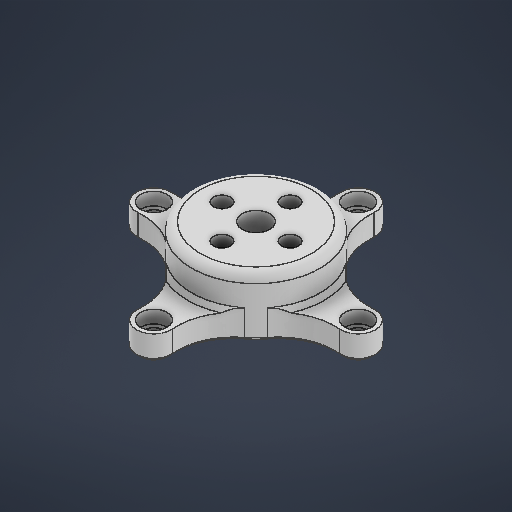
# Autodesk Inventor part: roter
Saved by Autodesk Inventor 2026.2 (Build 302298010, 298A)
## iProperties
Created: 2026-04-12
Part Number: roter
Material: 일반
Document SubType Name: Modeling
Designer: work
Density: 1 g/cm^3
Appearance: 기본값
Author: work
Autodesk Inventor part; units mm, degrees
ref_plane "YZ Plane" through (0, 0, 0) normal (1, 0, 0) x (0, 1, 0)
ref_plane "XZ Plane" through (0, 0, 0) normal (0, 1, 0) x (-1, 0, 0)
ref_plane "XY Plane" through (0, 0, 0) normal (0, 0, 1) x (1, 0, 0)
sketch "스케치1" plane through (0, 0, 0) normal (0, 1, 0) x (-1, 0, 0)
  circle A0 centre (0, 0) radius 24 construction
  circle A1 centre (24, 0) radius 2.05
  line L0 (0, 0) -> (24, 0) construction
  circle A2 centre (24, 0) radius 4.05
  circle A3 centre (0, 0) radius 3.25
  circle A4 centre (0, 0) radius 8 construction
  circle A5 centre (8, 0) radius 2
  circle A6 centre (0, 0) radius 15.05
  arc A7 (11.909488, 9.201445) -> (23.658281, 4.035558) centre (22.526272, 17.404127) ccw
  arc A8 (23.658281, -4.035558) -> (11.909488, -9.201445) centre (22.526272, -17.404127) ccw
  circle A9 centre (0, 24) radius 2.05
  line L1 (0, 0) -> (0, 24) construction
  circle A10 centre (0, 24) radius 4.05
  arc A11 (-9.201445, 11.909488) -> (-4.035558, 23.658281) centre (-17.404127, 22.526272) ccw
  arc A12 (4.035558, 23.658281) -> (9.201445, 11.909488) centre (17.404127, 22.526272) ccw
  circle A13 centre (0, 8) radius 2
  circle A14 centre (-24, 0) radius 2.05
  line L2 (0, 0) -> (-24, 0) construction
  circle A15 centre (-24, 0) radius 4.05
  arc A16 (-11.909488, -9.201445) -> (-23.658281, -4.035558) centre (-22.526272, -17.404127) ccw
  arc A17 (-23.658281, 4.035558) -> (-11.909488, 9.201445) centre (-22.526272, 17.404127) ccw
  circle A18 centre (-8, 0) radius 2
  circle A19 centre (0, -24) radius 2.05
  line L3 (0, 0) -> (0, -24) construction
  circle A20 centre (0, -24) radius 4.05
  arc A21 (9.201445, -11.909488) -> (4.035558, -23.658281) centre (17.404127, -22.526272) ccw
  arc A22 (-4.035558, -23.658281) -> (-9.201445, -11.909488) centre (-17.404127, -22.526272) ccw
  circle A23 centre (0, -8) radius 2
  point P0 (11.909488, -9.201445)
  point P1 (23.658281, -4.035558)
  point P2 (-9.201445, -11.909488)
  point P3 (-4.035558, -23.658281)
  point P4 (-11.909488, 9.201445)
  point P5 (-23.658281, 4.035558)
  point P6 (-11.909488, -9.201445)
  point P7 (-9.201445, 11.909488)
  point P8 (9.201445, 11.909488)
  point P9 (4.035558, 23.658281)
  dimension "d4" = 16
  dimension "d6" = 30.1
  dimension "d0" = 48
  dimension "d1" = 4.1
  dimension "d2" = 2
  dimension "d3" = 6.5
  dimension "d5" = 4
  dimension "d9" = 360
  constraints: 18 centre point, 18 point on circle, 8 coincident, 8 end point, 4 point on line, 3 symmetric about line, 1 horizontal, 1 horizontal alignment, 85 other
  measures "d0" diameter of A0
  measures "d1" diameter of A1
  measures "d3" diameter of A3
  measures "d5" diameter of A5
extrude "돌출1" add sketch "스케치1" along normal blind 6 contours A2 | A2 A8 A6 A7 | A6 A11 A10 A12 | A21 A20 A22 A6 | A10 | A20 | A6 A16 A15 A17 | A15
extrude "돌출2" add sketch "스케치1" along normal blind 14 contours A6
chamfer "모따기1" distance 1 angle 45 21 edges at (15.05, 6, 0) (0, 6, 15.05) (0, 6, -15.05) (-14.2432, 6, 4.8613) (-14.2432, 6, -4.8613) (5.1225, 0, 17.1261) (10.642, 0, 10.642) (17.1261, 0, 5.1225) (28.05, 0, 0) (17.1261, 0, -5.1225) (10.642, 0, -10.642) (5.1225, 0, -17.1261) (0, 0, -28.05) (-5.1225, 0, -17.1261) (-10.642, 0, -10.642) (-17.1261, 0, -5.1225) (-28.05, 0, 0) (-17.1261, 0, 5.1225) (-10.642, 0, 10.642) (-5.1225, 0, 17.1261) (0, 0, 28.05)
sketch "스케치2" plane through (0, 6, 0) normal (0, 1, 0) x (1, 0, 0)
  arc A0 (-6.536796, -14.65854) -> (6.536796, -14.65854) centre (0, 0) ccw
  arc A1 (-4.035558, -23.658281) -> (-6.536796, -14.65854) centre (-17.404127, -22.526272) ccw
  arc A2 (-4.035558, -23.658281) -> (4.035558, -23.658281) centre (0, -24) ccw
  arc A3 (6.536796, -14.65854) -> (4.035558, -23.658281) centre (17.404127, -22.526272) ccw
  circle A4 centre (0, -24) radius 2.05
  arc A5 (-14.65854, 6.536796) -> (-14.65854, -6.536796) centre (0, 0) ccw
  arc A6 (-23.658281, 4.035558) -> (-14.65854, 6.536796) centre (-22.526272, 17.404127) ccw
  arc A7 (-23.658281, 4.035558) -> (-23.658281, -4.035558) centre (-24, 0) ccw
  arc A8 (-14.65854, -6.536796) -> (-23.658281, -4.035558) centre (-22.526272, -17.404127) ccw
  circle A9 centre (-24, 0) radius 2.05
  arc A10 (14.65854, -6.536796) -> (14.65854, 6.536796) centre (0, 0) ccw
  arc A11 (23.658281, -4.035558) -> (14.65854, -6.536796) centre (22.526272, -17.404127) ccw
  arc A12 (23.658281, -4.035558) -> (23.658281, 4.035558) centre (24, 0) ccw
  arc A13 (14.65854, 6.536796) -> (23.658281, 4.035558) centre (22.526272, 17.404127) ccw
  circle A14 centre (24, 0) radius 2.05
  arc A15 (3.039124, 23.742656) -> (8.590053, 11.11816) centre (17.404127, 22.526272) ccw
  arc A16 (6.536796, 14.65854) -> (-6.536796, 14.65854) centre (0, 0) ccw
  arc A17 (4.035558, 23.658281) -> (6.536796, 14.65854) centre (17.404127, 22.526272) ccw
  arc A18 (4.035558, 23.658281) -> (-4.035558, 23.658281) centre (0, 24) ccw
  arc A19 (-6.536796, 14.65854) -> (-4.035558, 23.658281) centre (-17.404127, 22.526272) ccw
  circle A20 centre (0, 24) radius 2.05
  arc A21 (3.039124, 23.742656) -> (-3.039124, 23.742656) centre (0, 24) ccw
  constraints: 4 coincident
hole "구멍1" at (0, 6, 24) at (-24, 6, 0) at (0, 6, -24) at (24, 6, 0) direction (0, -1, 0) diameter 3.8 end through all counterbore diameter 6.2 counterbore depth 3
fillet "모깎기1" radius 2 1 edges at (15.05, 14, 0)
